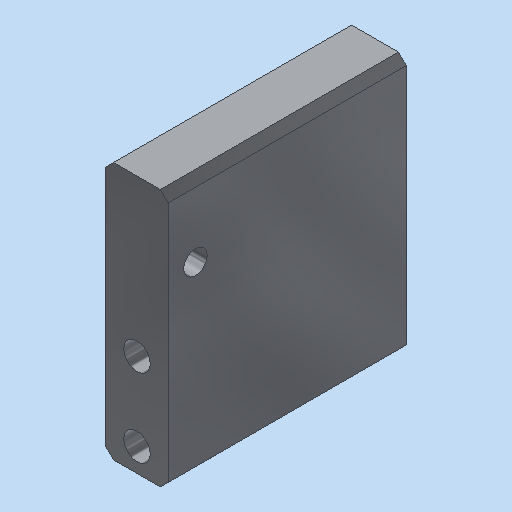
# Autodesk Inventor part: MM0868AN100_G80_110
Saved by Autodesk Inventor 2023.3 (Build 273359000, 359)
## iProperties
RuleStatus: InUse
Created: 2020-12-08
Part Number: MM0868AN100_G80_110
Material: 3.3547 AlMg4,5Mn0,7 - AW 5083
Description: =<RBPARTNOTITLE2>
Document SubType Name: Modeling
Designer: RUD
Mass: 19.9277 g
Surface Area: 36.3004 cm^2
Volume: 7.38062 cm^3
Density: 2.7 g/cm^3
Appearance: Aluminium AnP
AnP_Kategorie: 1
AnP_Material: =<Material>
AnP_TemplVers: 20200821
RBDOCUMENTTYPE: DRF
RBDOCUMENTVERSION: 00
RBDRAWINGMAINSCALE: 1:1
RBDRAWINGMISSINGSPEC: --
RBDRAWINGVOLUME: --
RBDSV1: 0850
RBGBEDGESIN1: +0,5
RBGBEDGESIN2: +0,2
RBGBEDGESOUT1: -0,3
RBGBEDGESOUT2: -0,1
RBMATERIAL: =<Material>
RBMATMEETS: --
RBMATNO: =<Part Number>
RBPARTMADEOF: Fl.40x8x34
RBPARTNO: SIEHE MNR
RBPARTNOTITLE1: manufactured part
RBPARTNOTITLE2: Anfertigungsteil
RBPARTSAFETYINDICATOR: --
RBSURFACE: anodised colourless
RBSURFACE2: eloxiert farblos
RBZEDGESNORM: ISO13715:2002-06
RBZGENDIMCLASS: m
RBZGENDIMNORM: ISO 2768-1:1989-11
RBZGENGEOCLASS: H
RBZGENGEONORM: ISO 2768-2:1989-11
RBZSURFACENORM: ISO13D2:2002-02
RBZTOLERANCENORM: ISO 14405-1:2010-12
Author: RUD
Keywords: =<RBPARTMADEOF>
Comments: =<RBSURFACE2>
Revision Number: 01
Autodesk Inventor part; units mm, degrees
ref_plane "YZ Plane" through (0, 0, 0) normal (1, 0, 0) x (0, 1, 0)
ref_plane "XZ Plane" through (0, 0, 0) normal (0, 1, 0) x (-1, 0, 0)
ref_plane "XY Plane" through (0, 0, 0) normal (0, 0, 1) x (1, 0, 0)
sketch "Skizze1" plane through (0, 0, 0) normal (0, 0, 1) x (1, 0, 0)
  line L0 (0, 36.6) -> (0, -9.6) projected
  line L1 (-5.6, 0) -> (5.6, 0) projected
  line L2 (-4, -3) -> (4, -3)
  line L3 (4, -3) -> (4, 30)
  line L4 (4, 30) -> (-4, 30)
  line L5 (-4, 30) -> (-4, -3)
  dimension "d0" = 3
  dimension "d1" = 8
  dimension "d2" = 30
  constraints: 8 end point, 2 parallel, 1 horizontal, 1 perpendicular, 1 other
  measures "d0" distance between parallel lines of L2 L1
  measures "d1" distance between parallel lines of L3 L5
  measures "d2" distance between parallel lines of L4 L1
extrude "Extrusion1" add sketch "Skizze1" along normal blind 30.5
sketch "Skizze2" plane through (0, 0, 30.5) normal (0, 0, 1) x (1, 0, 0)
  line L0 (0, 36.6) -> (0, -9.6) projected
  line L1 (-5.6, 0) -> (5.6, 0) projected
  point P0 (0, 0)
  point P1 (0, 10)
  dimension "d5" = 10
  constraints: 2 point on line, 1 midpoint
  measures "d5" distance from line of L1 point (0, 10)
hole "Bohrung1" at (0, 0, 30.5) at (0, 10, 30.5) direction (0, 0, -1) diameter 3.4 end through all
sketch "Skizze3" plane through (-4, -3, 0) normal (-1, 0, 0) x (0, 0, 1)
  line L0 (30.5, 33) -> (30.5, 0) projected
  line L1 (-6.1, 3) -> (36.6, 3) projected
  point P0 (27, 23.7)
  dimension "d13" = 20.7
  dimension "d14" = 3.5
  measures "d13" distance from line of L1 point (27, 23.7)
  measures "d14" distance from line of L0 point (27, 23.7)
hole "Bohrung2" at (-4, 20.7, 27) direction (1, 0, 0) diameter 3 end through all
chamfer "Fase1" distance 1 angle 45 4 edges at (-4, 30, 15.25) (4, 30, 15.25) (4, -3, 15.25) (-4, -3, 15.25)
